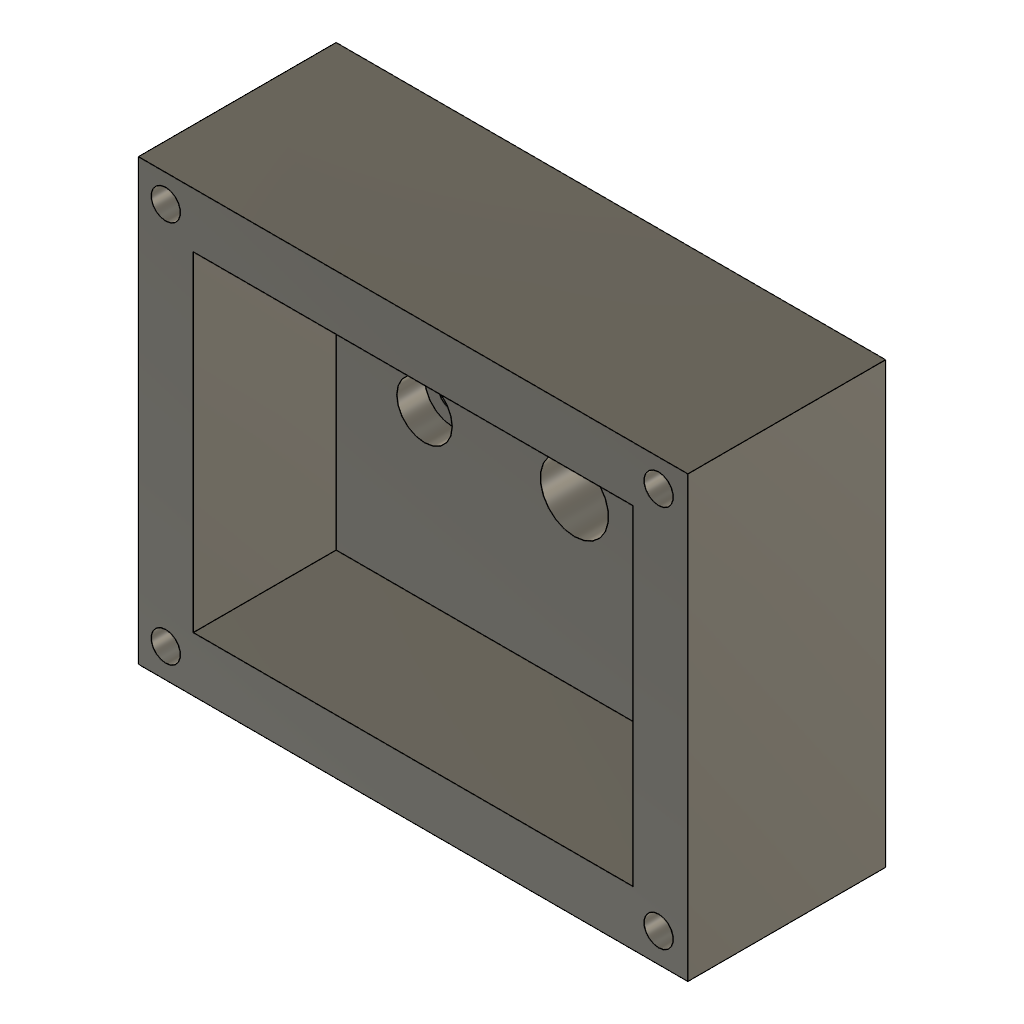
Gearbox_Housing (Autodesk Fusion 360 design; units mm, degrees)
part number: 2026-10-29-00-35-07-078
Autodesk Fusion 360 part; units mm, degrees
note: some values were not read from the file. Set by a fixed rule: which face or edge a step refers to.
sketch "Sketch1" plane through (0, 0, 0) normal (0, 1, 0) x (1, 0, 0)
  line L0 (0.8029, 0) -> (64.3029, 0)
  line L1 (64.3029, 0) -> (64.3029, -50.8)
  line L2 (64.3029, -50.8) -> (0.8029, -50.8)
  line L3 (0.8029, -50.8) -> (0.8029, 0)
  dimension "d1" = 63.5
  dimension "d2" = 50.8
  constraint horizontal L0
  constraint vertical L1
  constraint horizontal L2
  constraint vertical L3
  measures "d1" distance of L0.start L0.end
  measures "d2" distance of L0.start L2.end
extrude "Extrude1" add sketch "Sketch1" along normal blind 25.4
shell "Shell1" thickness 6.35 removed faces 1 at (21.9696, 25.4, 33.8667)
extrude "Extrude2" cut 1 faces at (41.0196, 25.4, 48.6833) along direction (0, -1, 0) blind 2.54
hole "Hole1" at (61.1279, 22.86, 47.625) direction (0, -1, 0) diameter 3.3782 depth 7.62 tip angle 180
pattern_linear "R-Pattern1" count 2 spacing 44.2468 along (0, 0, -1) count 2 spacing 56.9468 along (-1, 0, 0) of "Hole1"
hole "Hole2" at (47.7421, 6.35, 25.4) direction (0, -1, 0) diameter 6.4008 depth 3.2258 tip angle 180
hole "Hole3" at (30.4193, 6.35, 25.4) direction (0, -1, 0) diameter 7.874 depth 7.62 tip angle 180
move_body "Move1" bodies 1 to x (-1, 0, 0) y (0, -1, 0) z (0, 0, 1) at (66.7314, 9.0489, 13.7864)
sketch "Sketch2" plane through (0, 5.9247, 0) normal (0, -1, 0) x (1, 0, 0)
  circle A0 centre (18.9893, 39.1864) radius 3.2004
  circle A1 centre (18.9893, 39.1864) radius 1.651
  dimension "d33" = 3.302
  constraint concentric A0 A1
  measures "d33" diameter of A1
extrude "Extrude3" cut sketch "Sketch2" against normal blind 27.94 contours A1
equation "House_Length = 2.5 in"
equation "House_Width = 2.00 in"
equation "House_Depth = 0.900 in"
equation "Shaft_Distance = 0.6871 in"
equation "Shell_to = 0.25 in"
equation "Press_Fit_J1 = 0.2514 in"
equation "Press_Fit_J2 = 0.304 in"
